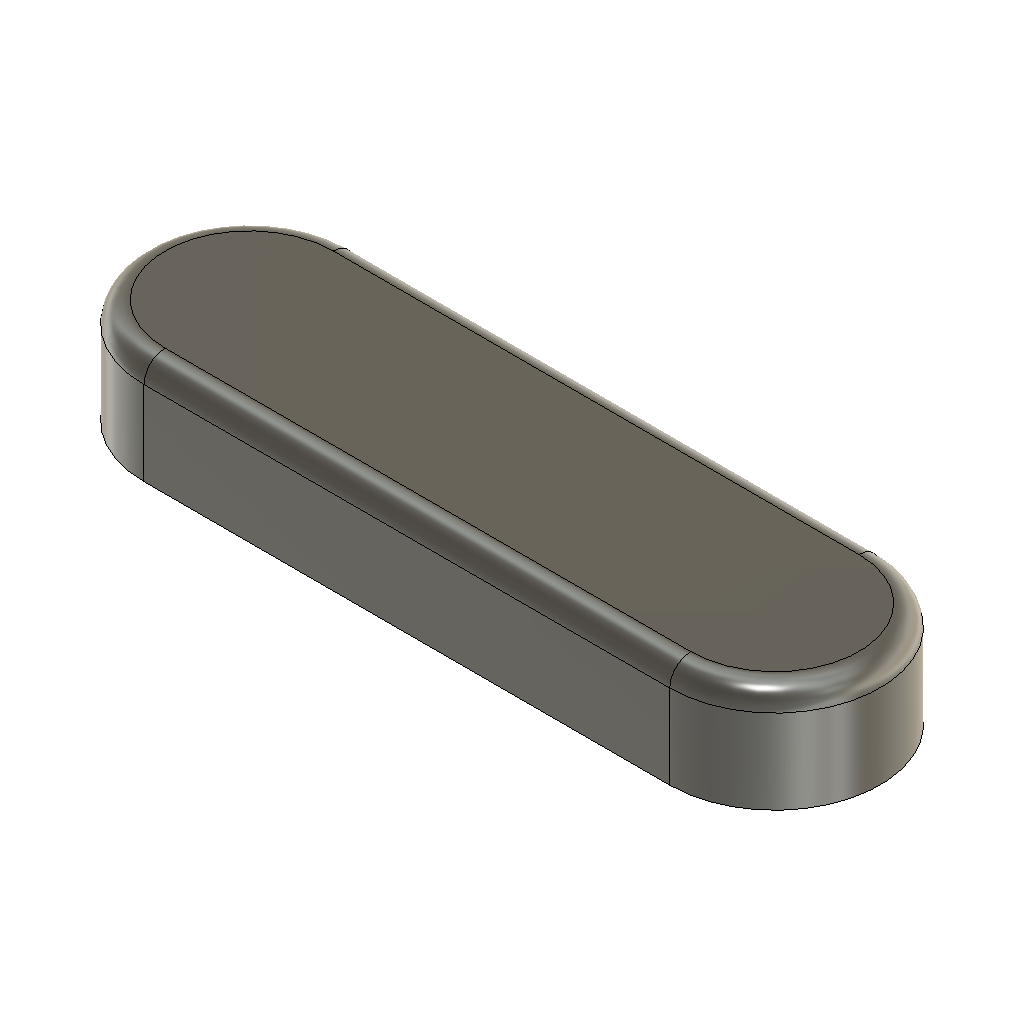
f2sc-test-fillet-chain (Autodesk Fusion 360 design; units mm, degrees)
part number: 2026-11-27-15-47-12-507
Autodesk Fusion 360 part; units mm, degrees
sketch "Sketch1" plane through (0, 0, 0) normal (0, 0, 1) x (1, 0, 0)
  line L0 (-25, 15) -> (25, 15)
  arc A0 (25, 15) -> (25, 35) centre (25, 25) ccw
  line L1 (25, 35) -> (-25, 35)
  arc A1 (-25, 35) -> (-25, 15) centre (-25, 25) ccw
  line L2 (-25, 25) -> (25, 25) construction
  constraint tangent L0 A0
  constraint tangent A0 L1
  constraint parallel L0 L1
  constraint tangent L1 A1
  constraint tangent L0 A1
  constraint horizontal L2
extrude "Extrude1" add sketch "Sketch1" along normal blind 10
fillet "Fillet1" radius 2 4 edges at (0, 35, 10) (-35, 25, 10) (0, 15, 10) (35, 25, 10)
